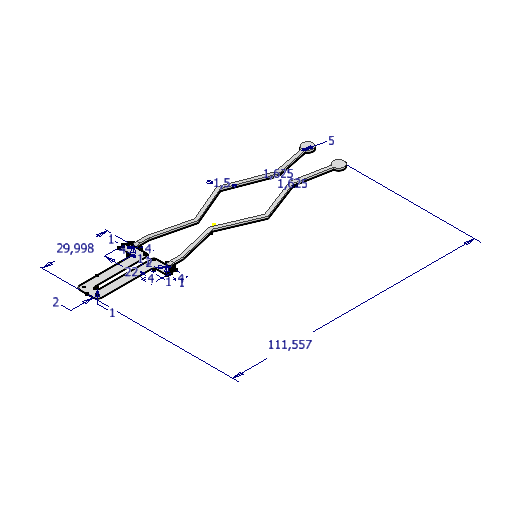
# Autodesk Inventor part: CortoFinale
Saved by Autodesk Inventor 2025.4 (Build 294407000, 407)
## iProperties
Created: 2026-10-06
Part Number: CortoFinale
Material: Generic
Document SubType Name: Modeling
Designer: gdira
Density: 1 g/cm^3
Appearance: Default
Author: gdira
Autodesk Inventor part; units mm, degrees
ref_plane "YZ Plane" through (0, 0, 0) normal (1, 0, 0) x (0, 1, 0)
ref_plane "XZ Plane" through (0, 0, 0) normal (0, 1, 0) x (-1, 0, 0)
ref_plane "XY Plane" through (0, 0, 0) normal (0, 0, 1) x (1, 0, 0)
sketch "Sketch1" plane through (0, 0, 0) normal (0, 1, 0) x (-1, 0, 0)
  line L0 (5.2346, -32.4703) -> (4.5792, -34.1849)
  line L1 (-3.2035, 32.1121) -> (-3.2035, 35.1121)
  arc A0 (-4.2035, 31.1121) -> (-3.2035, 32.1121) centre (-4.2035, 32.1121) ccw
  line L2 (-8.2036, 31.1121) -> (-4.2035, 31.1121)
  arc A1 (-0.2035, 27.1121) -> (0.7965, 28.1121) centre (-0.2035, 28.1121) ccw
  line L3 (-9.2036, 28.1121) -> (-9.2036, 30.1121)
  line L4 (12.308, -15.5407) -> (12.8654, -15.3044)
  line L5 (13.6014, -14.7811) -> (11.9961, -14.7811)
  line L6 (4.6975, -33.8755) -> (12.2938, -14.0021)
  line L7 (-1.3221, -33.3062) -> (-8.7008, -14.0021)
  line L8 (4.403, 3.1269) -> (11.9961, -14.7811)
  line L9 (-0.81, 3.1269) -> (-8.4031, -14.7811)
  line L10 (-10.0084, -14.7811) -> (-2.3759, 3.22)
  line L11 (-3.2035, 55.1189) -> (-3.2035, 35.1121)
  line L12 (6.7965, 55.1189) -> (6.7965, 35.1399)
  line L13 (13.6014, -14.7811) -> (5.9689, 3.22)
  line L14 (-1.2035, 57.1189) -> (4.7965, 57.1189)
  arc A2 (-1.2035, 57.1189) -> (-3.2035, 55.1189) centre (-1.2035, 55.1189) ccw
  arc A3 (6.7965, 55.1189) -> (4.7965, 57.1189) centre (4.7965, 55.1189) ccw
  line L15 (-0.2035, 27.1121) -> (-4.2035, 27.1121)
  line L16 (11.7965, 27.12) -> (12.802, 27.1219)
  line L17 (12.7964, 28.1198) -> (12.7964, 30.1217)
  line L18 (11.7964, 31.1217) -> (7.7965, 31.1217)
  arc A4 (-9.2036, 28.1121) -> (-8.2036, 27.1121) centre (-8.2036, 28.1121) ccw
  arc A5 (-8.2036, 31.1121) -> (-9.2036, 30.1121) centre (-8.2036, 30.1121) ccw
  arc A6 (12.7964, 30.1217) -> (11.7964, 31.1217) centre (11.7964, 30.1217) ccw
  line L19 (6.7965, 32.1217) -> (6.7965, 38.6941)
  arc A7 (11.7982, 27.1199) -> (12.7964, 28.1198) centre (11.7964, 28.1198) ccw
  line L20 (0.7965, 52.1189) -> (0.7965, 28.1121)
  line L21 (2.7965, 28.1174) -> (2.7965, 52.1189)
  arc A8 (2.7965, 52.1189) -> (1.7965, 53.1189) centre (1.7965, 52.1189) ccw
  arc A9 (1.7965, 53.1189) -> (0.7965, 52.1189) centre (1.7965, 52.1189) ccw
  line L22 (8.7965, 21.1245) -> (8.7965, 25.6208)
  line L23 (10.3028, 25.1208) -> (10.3028, 21.1245)
  arc A10 (6.7965, 32.1217) -> (7.7965, 31.1217) centre (7.7965, 32.1217) ccw
  line L24 (4.403, 3.1269) -> (8.8369, 21.4443)
  line L25 (10.3028, 21.1245) -> (5.9689, 3.22)
  line L26 (12.2992, 27.1208) -> (11.3028, 27.1208)
  line L27 (2.7965, 28.1208) -> (2.7965, 28.5181)
  arc A11 (2.7965, 28.1208) -> (3.7965, 27.1208) centre (3.7965, 28.1208) ccw
  line L28 (10.3028, 25.1208) -> (10.3028, 26.1208)
  line L29 (8.7965, 25.6208) -> (8.7965, 26.1208)
  line L30 (3.7965, 27.1208) -> (7.7965, 27.1208)
  arc A12 (8.7965, 26.1208) -> (7.7965, 27.1208) centre (7.7965, 26.1208) ccw
  line L31 (12.2992, 27.1208) -> (4.6975, 27.1208)
  arc A13 (11.3028, 27.1208) -> (10.3028, 26.1208) centre (11.3028, 26.1208) ccw
  arc A14 (-4.2035, 27.1121) -> (-5.2035, 26.1121) centre (-4.2035, 26.1121) ccw
  line L32 (-5.2035, 21.1245) -> (-5.2035, 26.1121)
  arc A15 (-6.7099, 26.1121) -> (-7.7099, 27.1121) centre (-7.7099, 26.1121) ccw
  line L33 (-7.7099, 27.1121) -> (-8.2036, 27.1121)
  line L34 (-1.2184, 27.1121) -> (-8.2036, 27.1121)
  line L35 (-6.7099, 26.1121) -> (-6.7099, 21.1245)
  line L36 (-0.81, 3.1269) -> (-5.244, 21.4443)
  line L37 (-6.7099, 21.1245) -> (-2.3759, 3.22)
  line L38 (9.6888, -51.9838) -> (6.1881, -34.2026)
  line L39 (-4.1704, -49.7774) -> (-1.1045, -33.8755)
  line L40 (-6.0959, -51.9838) -> (-4.5959, -51.9838)
  line L41 (9.6888, -51.9838) -> (8.1888, -51.9838)
  arc A16 (-5.6063, -49.4974) -> (-4.1704, -49.7774) centre (-5.3459, -51.9838) ccw
  arc A17 (7.7634, -49.7774) -> (9.1993, -49.4974) centre (8.9388, -51.9838) ccw
  line L42 (4.6975, -33.8755) -> (5.0506, -34.7751)
  line L43 (-1.1045, -33.8755) -> (-1.4576, -34.7751)
  line L44 (-1.6416, -32.4703) -> (-1.1045, -33.8755)
  line L45 (13.6014, -14.7811) -> (6.1846, -34.1849)
  line L46 (5.5108, -35.9477) -> (5.2357, -36.6673)
  line L47 (-10.0084, -14.7811) -> (-2.5916, -34.1849)
  line L48 (-1.9178, -35.9477) -> (-1.6428, -36.6673)
  line L49 (-3.0043, -33.1053) -> (-2.5916, -34.1849)
  line L50 (6.3888, -35.222) -> (6.0913, -33.7111)
  line L51 (6.0913, -33.7111) -> (6.1846, -34.1849)
  line L52 (6.4127, -33.5882) -> (6.1846, -34.1849)
  line L53 (6.1846, -34.1849) -> (4.5596, -34.1849)
  line L54 (7.7634, -49.7774) -> (4.5596, -34.1849)
  line L55 (-1.1045, -33.8755) -> (-2.7295, -33.8755)
  line L56 (-5.6063, -49.4974) -> (-2.7295, -33.8755)
  point P0 (0, 0)
  point P1 (-9.2036, 31.1121)
  point P2 (-9.2036, 29.1121)
  point P3 (-9.2036, 27.1121)
  point P4 (6.4768, 47.5449)
  point P5 (12.2992, 27.1209)
  point P6 (-6.7099, 27.1121)
  point P7 (6.7908, 27.1108)
  point P8 (12.7964, 31.1217)
  point P9 (12.7964, 29.1208)
  point P10 (6.1903, 3.9982)
  point P11 (8.7965, 27.1208)
  point P12 (-5.2035, 25.6208)
  point P13 (-5.2035, 25.6208)
  point P14 (-6.7099, 25.1208)
  point P15 (-2.5973, 3.9982)
  point P16 (6.0764, -34.846)
  point P17 (6.1891, -33.639)
  point P18 (-2.824, -33.639)
  point P19 (-2.7112, -34.846)
  point P20 (1.7965, 57.1189)
  point P21 (-5.8243, -54.4376)
  point P22 (11.3028, 27.1208)
  point P23 (11.8393, 27.1208)
  point P24 (-5.2035, 21.2772)
  point P25 (1.7965, 53.1189)
  point P26 (8.7965, 21.2772)
  point P27 (4.9151, -33.3062)
  point P28 (7.7965, 27.1208)
  point P29 (7.7965, 27.1208)
  point P30 (-2.7099, -33.8755)
  point P31 (4.8189, -34.1849)
  dimension "d0" = 4
  dimension "d1" = 4
  dimension "d2" = 2
  dimension "d3" = 29.998
  dimension "d4" = 2
  dimension "d5" = 4
  dimension "d6" = 1
  dimension "d7" = 1
  dimension "d8" = 22
  dimension "d9" = 1.5
  dimension "d10" = 1
  dimension "d11" = 1
  dimension "d12" = 1
  dimension "d13" = 1
  dimension "d14" = 4
  dimension "d15" = 5
  dimension "d16" = 111.5566
  dimension "d22" = 1.625
  dimension "d24" = 1.625
  constraints: 114 end point, 38 point on circle, 36 point on line, 27 tangent, 18 centre point, 8 equal radius, 8 horizontal, 8 parallel, 6 perpendicular, 5 midpoint, 4 collinear, 4 vertical, 6 other
  measures "d0" distance between parallel lines of L21 L12
  measures "d1" distance between parallel lines of L11 L20
  measures "d2" distance between parallel lines of L20 L21
  measures "d3" distance from line of point (12.299, 27.121) L14
  measures "d4" radius of A2
  measures "d5" distance of point (-9.204, 27.112) point (-9.204, 31.112)
  measures "d6" radius of A0
  measures "d7" radius of A9
  measures "d8" distance of point (-9.204, 29.112) point (12.796, 29.121)
  measures "d9" distance of L45.start L4.start
  measures "d10" radius of A13
  measures "d11" radius of A12
  measures "d12" radius of A14
  measures "d13" radius of A15
  measures "d14" distance of L30.start L30.end
  measures "d15" diameter of A17
  measures "d16" vertical distance of point (1.796, 57.119) point (-5.824, -54.438)
  measures "d22" distance of L45.end L53.end
  measures "d24" distance of L44.end L55.end
extrude "Extrusion1" add sketch "Sketch1" along normal blind 0.15 contours L30 A11 L21 A8 A9 L20 A1 L15 L34 L33 A4 L3 A5 L2 A0 L1 L11 A2 L14 A3 L12 L19 A10 L18 A6 L17 A7 L26 L31
extrude "Extrusion2" add sketch "Sketch1" along normal blind 1 contours L6 L5 L45 L53 L42 L0 | L8 L24 L22 L29 A12 L31 A13 L28 L23 L25 L13 L5 | L53 L50 L38 A17 L54 | A14 L32 L36 L9 L7 L44 L55 L47 L10 L37 L35 A15 L34 | L39 A16 L56 L55
fillet "Fillet1" radius 2 2 edges at (-9.5497, 1, 27.1208) (5.9567, 1, 27.1121)
body "Solid1"
